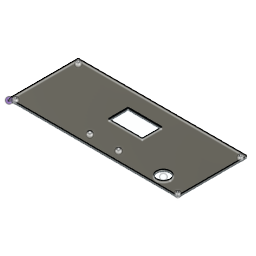
Resistor Box Front Panel (Autodesk Fusion 360 design; units mm, degrees)
Autodesk Fusion 360 part; units mm, degrees
sketch "Sketch1" plane through (0, 0, 0) normal (0, 0, 1) x (1, 0, 0)
  line L0 (0, 0) -> (234.75, 0)
  line L1 (234.75, 0) -> (234.75, 96.2)
  line L2 (234.75, 96.2) -> (0, 96.2)
  line L3 (0, 96.2) -> (0, 0)
  circle A0 centre (4.3, 91.9) radius 1.5625
  circle A1 centre (230.45, 91.9) radius 1.5625
  circle A2 centre (230.45, 4.3) radius 1.5625
  circle A3 centre (4.3, 4.3) radius 1.5625
  line L4 (94.375, 71.2) -> (140.375, 71.2)
  line L5 (140.375, 71.2) -> (140.375, 44.95)
  line L6 (140.375, 44.95) -> (94.375, 44.95)
  line L7 (94.375, 44.95) -> (94.375, 71.2)
  circle A4 centre (199.75, 15) radius 9.5
  circle A5 centre (97.375, 15) radius 2.0625
  circle A6 centre (137.375, 15) radius 2.0625
  dimension "d1" = 234.75
  dimension "d2" = 96.2
  dimension "d3" = 3.125
  dimension "d4" = 4.3
  dimension "d5" = 4.3
  dimension "d6" = 4.3
  dimension "d7" = 4.3
  dimension "d8" = 4.3
  dimension "d9" = 4.3
  dimension "d10" = 4.3
  dimension "d11" = 4.3
  dimension "d12" = 46
  dimension "d13" = 26.25
  dimension "d14" = 25
  dimension "d15" = 94.375
  dimension "d16" = 19
  dimension "d17" = 35
  dimension "d18" = 15
  dimension "d19" = 4.125
  dimension "d20" = 40
  dimension "d21" = 15
  dimension "d22" = 15
  dimension "d23" = 97.375
  constraint horizontal L0
  constraint vertical L1
  constraint horizontal L2
  constraint vertical L3
  constraint coincident L0.start L3.end
  constraint equal A2 A3
  constraint equal A1 A2
  constraint equal A0 A1
  constraint horizontal L4
  constraint vertical L5
  constraint horizontal L6
  constraint vertical L7
  constraint equal A5 A6
  measures "d1" distance of L0.start L0.end
  measures "d2" distance of L0.start L2.end
  measures "d3" diameter of A0
  measures "d4" distance of L2 A0.centre
  measures "d5" distance of L3 A0.centre
  measures "d6" distance of L0 A3.centre
  measures "d7" distance of L3 A3.centre
  measures "d8" distance of L1 A2.centre
  measures "d9" distance of L0 A2.centre
  measures "d10" distance of L1 A1.centre
  measures "d11" distance of L2 A1.centre
  measures "d12" distance of L4.start L4.end
  measures "d13" distance of L4.end L5.end
  measures "d14" distance of L2 L4
  measures "d15" distance of L3 L7
  measures "d16" diameter of A4
  measures "d17" distance of L1 A4.centre
  measures "d18" distance of L0 A4.centre
  measures "d19" diameter of A5
  measures "d20" distance of A5.centre A6.centre
  measures "d21" distance of L0 A6.centre
  measures "d22" distance of L0 A5.centre
  measures "d23" distance of L3 A5.centre
extrude "Extrude1" add sketch "Sketch1" along normal blind 2.5
chamfer "Chamfer1" distance 0.5 angle 45 4 edges at (0, 0, 1.25) (0, 96.2, 1.25) (234.75, 96.2, 1.25) (234.75, 0, 1.25)
chamfer "Chamfer2" distance 0.5 angle 45 4 edges at (117.375, 71.2, 2.5) (140.375, 58.075, 2.5) (117.375, 44.95, 2.5) (94.375, 58.075, 2.5)
equation "d15 = ( ( 234.75 / 2 ) * 1 mm ) - ( 46 / 2 ) * 1 mm"
equation "d23 = ( ( 234.75 / 2 ) * 1 mm ) - 20 * 1 mm"
named bodies: "ResistorBX_FP"
